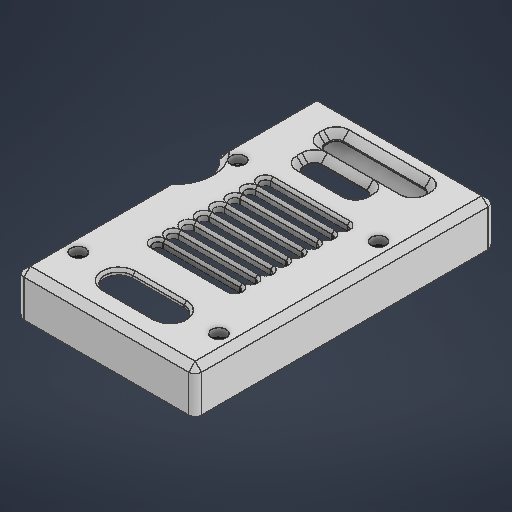
# Autodesk Inventor part: m3 case
Saved by Autodesk Inventor 2027.1 (Build 311270010, 270A)
## iProperties
Created: 2026-10-13
Part Number: m3 case
Material: 일반
Document SubType Name: Modeling
Designer: work
Density: 1 g/cm^3
Appearance: 기본값
Author: work
Autodesk Inventor part; units mm, degrees
ref_plane "YZ Plane" through (0, 0, 0) normal (1, 0, 0) x (0, 1, 0)
ref_plane "XZ Plane" through (0, 0, 0) normal (0, 1, 0) x (-1, 0, 0)
ref_plane "XY Plane" through (0, 0, 0) normal (0, 0, 1) x (1, 0, 0)
sketch "스케치1" plane through (0, 0, 0) normal (0, 1, 0) x (-1, 0, 0)
  line L0 (0, 0) -> (69.41, 0)
  line L1 (69.41, 0) -> (69.41, -117.01)
  line L2 (69.41, -117.01) -> (0, -117.01)
  line L3 (0, -117.01) -> (0, 0)
  line L4 (62.205, -16.5) -> (7.205, -16.5) construction
  line L5 (7.205, -16.5) -> (7.205, -78.9) construction
  line L6 (7.205, -78.9) -> (62.205, -78.9) construction
  line L7 (62.205, -78.9) -> (62.205, -16.5) construction
  line L8 (66.91, -114.51) -> (66.91, -2.5)
  line L9 (66.91, -2.5) -> (2.5, -2.5)
  line L10 (2.5, -2.5) -> (2.5, -114.51)
  line L11 (2.5, -114.51) -> (66.91, -114.51)
  circle A0 centre (7.205, -16.5) radius 1.55
  circle A1 centre (62.205, -16.5) radius 1.55
  circle A2 centre (62.205, -78.9) radius 1.55
  circle A3 centre (7.205, -78.9) radius 1.55
  circle A4 centre (7.205, -16.5) radius 2.5
  circle A5 centre (7.205, -78.9) radius 2.5
  circle A6 centre (62.205, -78.9) radius 2.5
  circle A7 centre (62.205, -16.5) radius 2.5
  line L12 (49.705, -89.4) -> (26.705, -89.4)
  line L13 (26.705, -89.4) -> (26.705, -96.4)
  line L14 (26.705, -96.4) -> (49.705, -96.4)
  line L15 (49.705, -96.4) -> (49.705, -89.4)
  line L16 (53.205, -101.4) -> (16.205, -101.4)
  line L17 (16.205, -101.4) -> (16.205, -108.4)
  line L18 (16.205, -108.4) -> (53.205, -108.4)
  line L19 (53.205, -108.4) -> (53.205, -101.4)
  line L20 (69.41, -68.9) -> (64.41, -68.9) construction
  arc A8 (69.41, -58.9) -> (69.41, -78.9) centre (76.91, -68.9) ccw
  point P0 (34.705, 0)
  point P1 (34.705, -16.5)
  point P2 (38.205, -89.4)
  point P3 (49.705, -92.9)
  point P4 (34.705, -108.4)
  point P5 (34.705, -114.51)
  point P6 (66.91, -68.9)
  point P7 (66.91, -76.4)
  point P8 (66.91, -61.4)
  dimension "d0" = 69.41
  dimension "d1" = 117.01
  dimension "d2" = 55
  dimension "d3" = 62.4
  dimension "d4" = 16.5
  dimension "d5" = 2.5
  dimension "d6" = 3.1
  dimension "d7" = 3.1
  dimension "d8" = 3.1
  dimension "d9" = 3.1
  dimension "d10" = 5
  dimension "d11" = 5
  dimension "d12" = 5
  dimension "d13" = 5
  dimension "d14" = 24
  dimension "d15" = 14
  dimension "d16" = 7
  dimension "d17" = 23
  dimension "d18" = 5
  dimension "d19" = 37
  dimension "d20" = 7
  dimension "d21" = 5
  dimension "d22" = 10
  dimension "d23" = 20
  constraints: 42 end point, 10 parallel, 9 centre point, 8 coincident, 7 midpoint, 5 horizontal, 5 perpendicular, 3 point on circle, 3 point on line, 2 vertical alignment, 1 line through centre, 3 other
  measures "d0" distance of L1.end L2.end
  measures "d1" distance of L0.end L1.end
  measures "d2" distance of L6.end L5.end
  measures "d3" distance of L6.end L4.start
  measures "d4" distance from line of point (34.705, 0) L4
  measures "d5" distance between parallel lines of L1 L8
  measures "d6" diameter of A0
  measures "d7" diameter of A3
  measures "d8" diameter of A1
  measures "d9" diameter of A2
  measures "d10" diameter of A4
  measures "d11" diameter of A5
  measures "d12" diameter of A6
  measures "d13" diameter of A7
  measures "d14" horizontal distance of L6.end point (38.205, -89.4)
  measures "d15" vertical distance of L6.end point (49.705, -92.9)
  measures "d16" distance of L14.end L12.start
  measures "d17" distance of L12.start L12.end
  measures "d18" distance between parallel lines of L14 L16
  measures "d19" distance of L16.start L16.end
  measures "d20" distance of L16.end L17.end
  measures "d21" distance of L20.start L20.end
  measures "d22" vertical distance of point (66.91, -68.9) L6.end
  measures "d23" distance of A8.end A8.start
extrude "돌출1" add sketch "스케치1" along normal blind 3 contours L0 L1 A8 L8 L9 L10 L11 L2 L3 | A8 L8 L11 L10 L9 | A4 | A5 | A6 | A7
extrude "돌출2" add sketch "스케치1" against normal blind 14 contours L0 L1 A8 L8 L9 L10 L11 L2 L3
extrude "돌출3" add sketch "스케치1" against normal blind 8 contours A4 | A5 | A6 | A7
fillet "모깎기1" radius 2.5 18 edges at (-69.41, -5.5, -117.01) (0, -5.5, 0) (-69.41, -5.5, 0) (-69.41, -5.5, -58.9) (-49.705, 1.5, -96.4) (-49.705, 1.5, -89.4) (0, -5.5, -117.01) (-53.205, 1.5, -101.4) (-53.205, 1.5, -108.4) (-16.205, 1.5, -108.4) (-16.205, 1.5, -101.4) (-69.41, -5.5, -78.9) (-26.705, 1.5, -96.4) (-26.705, 1.5, -89.4) (-66.91, -7, -2.5) (-66.91, -7, -114.51) (-2.5, -7, -114.51) (-2.5, -7, -2.5)
chamfer "모따기1" distance 2.5 angle 45 28 edges at (-48.9728, 3, -95.6678) (-49.705, 3, -92.9) (-48.9728, 3, -90.1322) (-38.205, 3, -89.4) (-27.4372, 3, -90.1322) (-26.705, 3, -92.9) (-27.4372, 3, -95.6678) (-38.205, 3, -96.4) (-52.4728, 3, -102.1322) (-34.705, 3, -101.4) (-16.9372, 3, -102.1322) (-16.205, 3, -104.9) (-16.9372, 3, -107.6678) (-34.705, 3, -108.4) (-52.4728, 3, -107.6678) (-53.205, 3, -104.9) (-64.41, 3, -68.9) (-69.1922, 3, -58.7403) (-69.41, 3, -30.1098) (-68.6778, 3, -0.7322) (-34.705, 3, 0) (-0.7322, 3, -0.7322) (0, 3, -58.505) (-0.7322, 3, -116.2778) (-34.705, 3, -117.01) (-68.6778, 3, -116.2778) (-69.41, 3, -97.2952) (-69.1922, 3, -79.0597)
sketch "스케치2" plane through (0, 0, 0) normal (0, -1, 0) x (1, 0, 0)
  line L0 (-19.705, -35.2) -> (-49.705, -35.2) construction
  line L1 (-19.705, -33.2) -> (-49.705, -33.2)
  line L2 (-49.705, -37.2) -> (-19.705, -37.2)
  arc A0 (-19.705, -37.2) -> (-19.705, -33.2) centre (-19.705, -35.2) ccw
  arc A1 (-49.705, -33.2) -> (-49.705, -37.2) centre (-49.705, -35.2) ccw
  line L3 (-64.41, -2.5) -> (-5, -2.5) projected
  line L4 (-19.205, -4.5) -> (-50.205, -4.5)
  line L5 (-50.205, -4.5) -> (-50.205, -25.2)
  line L6 (-50.205, -25.2) -> (-19.205, -25.2)
  line L7 (-19.205, -25.2) -> (-19.205, -4.5)
  arc A2 (-49.705, -39.2) -> (-49.705, -43.2) centre (-49.705, -41.2) ccw
  line L8 (-49.705, -43.2) -> (-19.705, -43.2)
  arc A3 (-19.705, -43.2) -> (-19.705, -39.2) centre (-19.705, -41.2) ccw
  line L9 (-19.705, -41.2) -> (-49.705, -41.2) construction
  line L10 (-19.705, -39.2) -> (-49.705, -39.2)
  arc A4 (-49.705, -45.2) -> (-49.705, -49.2) centre (-49.705, -47.2) ccw
  line L11 (-49.705, -49.2) -> (-19.705, -49.2)
  arc A5 (-19.705, -49.2) -> (-19.705, -45.2) centre (-19.705, -47.2) ccw
  line L12 (-19.705, -47.2) -> (-49.705, -47.2) construction
  line L13 (-19.705, -45.2) -> (-49.705, -45.2)
  arc A6 (-49.705, -51.2) -> (-49.705, -55.2) centre (-49.705, -53.2) ccw
  line L14 (-49.705, -55.2) -> (-19.705, -55.2)
  arc A7 (-19.705, -55.2) -> (-19.705, -51.2) centre (-19.705, -53.2) ccw
  line L15 (-19.705, -53.2) -> (-49.705, -53.2) construction
  line L16 (-19.705, -51.2) -> (-49.705, -51.2)
  arc A8 (-49.705, -57.2) -> (-49.705, -61.2) centre (-49.705, -59.2) ccw
  line L17 (-49.705, -61.2) -> (-19.705, -61.2)
  arc A9 (-19.705, -61.2) -> (-19.705, -57.2) centre (-19.705, -59.2) ccw
  line L18 (-19.705, -59.2) -> (-49.705, -59.2) construction
  line L19 (-19.705, -57.2) -> (-49.705, -57.2)
  arc A10 (-49.705, -63.2) -> (-49.705, -67.2) centre (-49.705, -65.2) ccw
  line L20 (-49.705, -67.2) -> (-19.705, -67.2)
  arc A11 (-19.705, -67.2) -> (-19.705, -63.2) centre (-19.705, -65.2) ccw
  line L21 (-19.705, -65.2) -> (-49.705, -65.2) construction
  line L22 (-19.705, -63.2) -> (-49.705, -63.2)
  arc A12 (-49.705, -69.2) -> (-49.705, -73.2) centre (-49.705, -71.2) ccw
  line L23 (-49.705, -73.2) -> (-19.705, -73.2)
  arc A13 (-19.705, -73.2) -> (-19.705, -69.2) centre (-19.705, -71.2) ccw
  line L24 (-19.705, -71.2) -> (-49.705, -71.2) construction
  line L25 (-19.705, -69.2) -> (-49.705, -69.2)
  arc A14 (-49.705, -75.2) -> (-49.705, -79.2) centre (-49.705, -77.2) ccw
  line L26 (-49.705, -79.2) -> (-19.705, -79.2)
  arc A15 (-19.705, -79.2) -> (-19.705, -75.2) centre (-19.705, -77.2) ccw
  line L27 (-19.705, -77.2) -> (-49.705, -77.2) construction
  line L28 (-19.705, -75.2) -> (-49.705, -75.2)
  line L29 (-44.705, -14.85) -> (-24.705, -14.85) construction
  line L30 (-44.705, -20.35) -> (-24.705, -20.35)
  line L31 (-24.705, -9.35) -> (-44.705, -9.35)
  arc A16 (-44.705, -9.35) -> (-44.705, -20.35) centre (-44.705, -14.85) ccw
  arc A17 (-24.705, -20.35) -> (-24.705, -9.35) centre (-24.705, -14.85) ccw
  line L32 (-50.205, -14.85) -> (-55.205, -14.85) construction
  line L33 (-50.205, -13.35) -> (-55.205, -13.35)
  line L34 (-55.205, -16.35) -> (-50.205, -16.35)
  arc A18 (-50.205, -16.35) -> (-50.205, -13.35) centre (-50.205, -14.85) ccw
  arc A19 (-55.205, -13.35) -> (-55.205, -16.35) centre (-55.205, -14.85) ccw
  point P0 (0, 0)
  point P1 (-34.705, -35.2)
  point P2 (-34.705, -2.5)
  point P3 (-34.705, -4.5)
  point P4 (-34.705, -2.5)
  point P5 (-34.705, -25.2)
  point P6 (-34.705, -41.2)
  point P7 (-34.705, -47.2)
  point P8 (-34.705, -53.2)
  point P9 (-34.705, -59.2)
  point P10 (-34.705, -65.2)
  point P11 (-34.705, -71.2)
  point P12 (-34.705, -77.2)
  point P13 (-34.705, -14.85)
  point P14 (-19.205, -14.85)
  point P15 (-52.705, -14.85)
  point P16 (-50.0005, -13.364)
  point P17 (-50.0005, -16.336)
  point P18 (-19.205, -14.85)
  dimension "d34" = 20.7
  dimension "d35" = 31
  dimension "d36" = 2
  dimension "d37" = 10
  dimension "d38" = 30
  dimension "d39" = 4
  dimension "d42" = 6
  dimension "d47" = 10
  dimension "d48" = 5
  dimension "d49" = 3
  constraints: 88 end point, 41 point on circle, 20 centre point, 13 tangent, 8 midpoint, 5 parallel, 4 horizontal, 3 vertical alignment, 1 horizontal alignment, 1 perpendicular, 1 vertical, 84 other
  measures "d34" distance of L4.end L5.end
  measures "d35" distance of L4.start L4.end
  measures "d36" distance between parallel lines of L3 L4
  measures "d37" distance of point (-34.705, -25.2) point (-34.705, -35.2)
  measures "d38" distance of L0.start L0.end
  measures "d39" distance between parallel lines of L1 L2
  measures "d42" distance of L0.end L9.end
  measures "d47" distance of point (-34.705, -14.85) L29.end
  measures "d48" distance of L32.start L32.end
  measures "d49" diameter of A19
extrude "돌출4" cut sketch "스케치2" against normal through all contours A0 L2 A1 L1 | A17 L30 A16 A18 L31 | A16 A18 | L10 A3 L8 A2 | L13 A5 L11 A4 | L16 A7 L14 A6 | L19 A9 L17 A8 | L22 A11 L20 A10 | L25 A13 L23 A12 | L28 A15 L26 A14
extrude "돌출5" cut sketch "스케치2" against normal blind 1 contours L7 A17 L31 A16 A18 L5 L4 | L7 L6 L5 A18 A16 L30 A17 | A18 A16 L5 | L5 L34 A19 L33 | A16 A18 L5
fillet "모깎기2" radius 2.5 2 edges at (-50.205, 0.5, -13.35) (-50.205, 0.5, -16.35)
fillet "모깎기3" radius 4 4 edges at (-19.205, 0.5, -4.5) (-19.205, 0.5, -25.2) (-50.205, 0.5, -25.2) (-50.205, 0.5, -4.5)
chamfer "모따기2" distance 1 angle 45 36 edges at (-34.705, 3, -20.35) (-19.205, 3, -14.85) (-34.705, 3, -9.35) (-50.205, 3, -14.85) (-34.705, 3, -33.2) (-51.705, 3, -35.2) (-34.705, 3, -37.2) (-17.705, 3, -35.2) (-51.705, 3, -41.2) (-34.705, 3, -43.2) (-17.705, 3, -41.2) (-34.705, 3, -39.2) (-51.705, 3, -47.2) (-34.705, 3, -49.2) (-17.705, 3, -47.2) (-34.705, 3, -45.2) (-51.705, 3, -53.2) (-34.705, 3, -55.2) (-17.705, 3, -53.2) (-34.705, 3, -51.2) (-51.705, 3, -59.2) (-34.705, 3, -61.2) (-17.705, 3, -59.2) (-34.705, 3, -57.2) (-51.705, 3, -65.2) (-34.705, 3, -67.2) (-17.705, 3, -65.2) (-34.705, 3, -63.2) (-51.705, 3, -71.2) (-34.705, 3, -73.2) (-17.705, 3, -71.2) (-34.705, 3, -69.2) (-51.705, 3, -77.2) (-34.705, 3, -79.2) (-17.705, 3, -77.2) (-34.705, 3, -75.2)
sketch "스케치3" plane through (0, 0, 0) normal (0, -1, 0) x (1, 0, 0)
  line L0 (-65.41, -57.5) -> (-52.91, -57.5)
  line L1 (-52.91, -57.5) -> (-52.91, -21.5)
  line L2 (-52.91, -21.5) -> (-65.41, -21.5)
  line L3 (-65.41, -21.5) -> (-65.41, -57.5)
  line L4 (-66.91, -61.4) -> (-66.91, -5) projected
  circle A0 centre (-62.205, -16.5) radius 1.55 projected
  point P0 (0, 0)
  dimension "d59" = 36
  dimension "d60" = 12.5
  dimension "d61" = 1.5
  dimension "d64" = 5
  constraints: 8 end point, 2 parallel, 1 horizontal, 1 perpendicular
  measures "d59" distance of L0.end L1.end
  measures "d60" distance of L1.end L2.end
  measures "d61" distance between parallel lines of L4 L3
  measures "d64" distance from line of A0.centre L2
extrude "돌출6" cut sketch "스케치3" against normal blind 2 contours L3 L2 L1 L0
sketch "스케치4" plane through (0, 0, 0) normal (0, -1, 0) x (1, 0, 0)
  line L0 (-65.41, -57.5) -> (-65.41, -21.5) projected
  line L1 (-65.41, -21.5) -> (-52.91, -21.5) projected
  line L2 (-52.91, -21.5) -> (-52.91, -57.5) projected
  line L3 (-52.91, -57.5) -> (-65.41, -57.5) projected
  arc A0 (-50.705, -101.4) -> (-53.205, -103.9) centre (-50.705, -103.9) ccw projected
  line L4 (-18.705, -101.4) -> (-50.705, -101.4) projected
  arc A1 (-16.205, -103.9) -> (-18.705, -101.4) centre (-18.705, -103.9) ccw projected
  line L5 (-16.205, -105.9) -> (-16.205, -103.9) projected
  arc A2 (-18.705, -108.4) -> (-16.205, -105.9) centre (-18.705, -105.9) ccw projected
  line L6 (-50.705, -108.4) -> (-18.705, -108.4) projected
  arc A3 (-53.205, -105.9) -> (-50.705, -108.4) centre (-50.705, -105.9) ccw projected
  line L7 (-53.205, -103.9) -> (-53.205, -105.9) projected
  arc A4 (-47.205, -89.4) -> (-49.705, -91.9) centre (-47.205, -91.9) ccw projected
  line L8 (-29.205, -89.4) -> (-47.205, -89.4) projected
  arc A5 (-26.705, -91.9) -> (-29.205, -89.4) centre (-29.205, -91.9) ccw projected
  line L9 (-26.705, -93.9) -> (-26.705, -91.9) projected
  arc A6 (-29.205, -96.4) -> (-26.705, -93.9) centre (-29.205, -93.9) ccw projected
  line L10 (-47.205, -96.4) -> (-29.205, -96.4) projected
  arc A7 (-49.705, -93.9) -> (-47.205, -96.4) centre (-47.205, -93.9) ccw projected
  line L11 (-49.705, -91.9) -> (-49.705, -93.9) projected
  circle A8 centre (-7.205, -78.9) radius 2.5 projected
  circle A9 centre (-7.205, -16.5) radius 2.5 projected
  circle A10 centre (-62.205, -78.9) radius 2.5 projected
  circle A11 centre (-62.205, -16.5) radius 2.5 projected
  arc A12 (-2.5, -5) -> (-5, -2.5) centre (-5, -5) ccw projected
  line L12 (-5, -2.5) -> (-64.41, -2.5) projected
  arc A13 (-64.41, -2.5) -> (-66.91, -5) centre (-64.41, -5) ccw projected
  line L13 (-66.91, -5) -> (-66.91, -61.4) projected
  arc A14 (-66.91, -76.4) -> (-66.91, -61.4) centre (-76.91, -68.9) ccw projected
  line L14 (-66.91, -76.4) -> (-66.91, -112.01) projected
  arc A15 (-66.91, -112.01) -> (-64.41, -114.51) centre (-64.41, -112.01) ccw projected
  line L15 (-64.41, -114.51) -> (-5, -114.51) projected
  arc A16 (-5, -114.51) -> (-2.5, -112.01) centre (-5, -112.01) ccw projected
  line L16 (-2.5, -112.01) -> (-2.5, -5) projected
  arc A17 (-19.705, -43.2) -> (-19.705, -39.2) centre (-19.705, -41.2) ccw projected
  line L17 (-19.705, -43.2) -> (-49.705, -43.2) projected
  arc A18 (-49.705, -39.2) -> (-49.705, -43.2) centre (-49.705, -41.2) ccw projected
  line L18 (-49.705, -39.2) -> (-19.705, -39.2) projected
  arc A19 (-19.705, -61.2) -> (-19.705, -57.2) centre (-19.705, -59.2) ccw projected
  line L19 (-19.705, -61.2) -> (-49.705, -61.2) projected
  arc A20 (-49.705, -57.2) -> (-49.705, -61.2) centre (-49.705, -59.2) ccw projected
  line L20 (-49.705, -57.2) -> (-19.705, -57.2) projected
  arc A21 (-19.705, -79.2) -> (-19.705, -75.2) centre (-19.705, -77.2) ccw projected
  line L21 (-19.705, -79.2) -> (-49.705, -79.2) projected
  arc A22 (-49.705, -75.2) -> (-49.705, -79.2) centre (-49.705, -77.2) ccw projected
  line L22 (-49.705, -75.2) -> (-19.705, -75.2) projected
  arc A23 (-19.705, -55.2) -> (-19.705, -51.2) centre (-19.705, -53.2) ccw projected
  line L23 (-19.705, -55.2) -> (-49.705, -55.2) projected
  arc A24 (-49.705, -51.2) -> (-49.705, -55.2) centre (-49.705, -53.2) ccw projected
  line L24 (-49.705, -51.2) -> (-19.705, -51.2) projected
  line L25 (-19.705, -37.2) -> (-49.705, -37.2) projected
  arc A25 (-49.705, -33.2) -> (-49.705, -37.2) centre (-49.705, -35.2) ccw projected
  line L26 (-49.705, -33.2) -> (-19.705, -33.2) projected
  arc A26 (-19.705, -37.2) -> (-19.705, -33.2) centre (-19.705, -35.2) ccw projected
  arc A27 (-19.705, -67.2) -> (-19.705, -63.2) centre (-19.705, -65.2) ccw projected
  line L27 (-19.705, -67.2) -> (-49.705, -67.2) projected
  arc A28 (-49.705, -63.2) -> (-49.705, -67.2) centre (-49.705, -65.2) ccw projected
  line L28 (-49.705, -63.2) -> (-19.705, -63.2) projected
  arc A29 (-19.705, -73.2) -> (-19.705, -69.2) centre (-19.705, -71.2) ccw projected
  line L29 (-19.705, -73.2) -> (-49.705, -73.2) projected
  arc A30 (-49.705, -69.2) -> (-49.705, -73.2) centre (-49.705, -71.2) ccw projected
  line L30 (-49.705, -69.2) -> (-19.705, -69.2) projected
  arc A31 (-19.705, -49.2) -> (-19.705, -45.2) centre (-19.705, -47.2) ccw projected
  line L31 (-19.705, -49.2) -> (-49.705, -49.2) projected
  arc A32 (-49.705, -45.2) -> (-49.705, -49.2) centre (-49.705, -47.2) ccw projected
  line L32 (-49.705, -45.2) -> (-19.705, -45.2) projected
  arc A33 (-50.205, -18.85) -> (-52.705, -16.35) centre (-52.705, -18.85) ccw projected
  line L33 (-52.705, -16.35) -> (-55.205, -16.35) projected
  arc A34 (-55.205, -13.35) -> (-55.205, -16.35) centre (-55.205, -14.85) ccw projected
  line L34 (-55.205, -13.35) -> (-52.705, -13.35) projected
  arc A35 (-52.705, -13.35) -> (-50.205, -10.85) centre (-52.705, -10.85) ccw projected
  line L35 (-50.205, -10.85) -> (-50.205, -8.5) projected
  arc A36 (-46.205, -4.5) -> (-50.205, -8.5) centre (-46.205, -8.5) ccw projected
  line L36 (-46.205, -4.5) -> (-23.205, -4.5) projected
  arc A37 (-19.205, -8.5) -> (-23.205, -4.5) centre (-23.205, -8.5) ccw projected
  line L37 (-19.205, -8.5) -> (-19.205, -21.2) projected
  arc A38 (-23.205, -25.2) -> (-19.205, -21.2) centre (-23.205, -21.2) ccw projected
  line L38 (-23.205, -25.2) -> (-46.205, -25.2) projected
  arc A39 (-50.205, -21.2) -> (-46.205, -25.2) centre (-46.205, -21.2) ccw projected
  line L39 (-50.205, -21.2) -> (-50.205, -18.85) projected
  circle A40 centre (-7.205, -78.9) radius 1.55 projected
  line L40 (-7.205, -78.9) -> (-2.5, -78.9) construction
  line L41 (-7.205, -83.9) -> (-2.5, -83.9)
  line L42 (-2.5, -73.9) -> (-7.205, -73.9)
  arc A41 (-7.205, -73.9) -> (-7.205, -83.9) centre (-7.205, -78.9) ccw
  arc A42 (-2.5, -83.9) -> (-2.5, -73.9) centre (-2.5, -78.9) ccw
  line L43 (-62.205, -78.9) -> (-66.91, -78.9) construction
  line L44 (-62.205, -76.4) -> (-66.91, -76.4)
  line L45 (-66.91, -81.4) -> (-62.205, -81.4)
  arc A43 (-62.205, -81.4) -> (-62.205, -76.4) centre (-62.205, -78.9) ccw
  arc A44 (-66.91, -76.4) -> (-66.91, -81.4) centre (-66.91, -78.9) ccw
  circle A45 centre (-62.205, -16.5) radius 1.55 projected
  line L46 (-62.205, -16.5) -> (-66.91, -16.5) construction
  line L47 (-62.205, -11.5) -> (-66.91, -11.5)
  line L48 (-66.91, -21.5) -> (-62.205, -21.5)
  arc A46 (-62.205, -21.5) -> (-62.205, -11.5) centre (-62.205, -16.5) ccw
  arc A47 (-66.91, -11.5) -> (-66.91, -21.5) centre (-66.91, -16.5) ccw
  circle A48 centre (-7.205, -16.5) radius 1.55 projected
  line L49 (-7.205, -16.5) -> (-2.5, -16.5) construction
  line L50 (-7.205, -21.5) -> (-2.5, -21.5)
  line L51 (-2.5, -11.5) -> (-7.205, -11.5)
  arc A49 (-7.205, -11.5) -> (-7.205, -21.5) centre (-7.205, -16.5) ccw
  arc A50 (-2.5, -21.5) -> (-2.5, -11.5) centre (-2.5, -16.5) ccw
  point P0 (0, 0)
  point P1 (-4.8525, -78.9)
  point P2 (-64.5575, -78.9)
  point P3 (-64.5575, -16.5)
  point P4 (-4.8525, -16.5)
  dimension "d65" = 10
  dimension "d67" = 10
  dimension "d68" = 10
  constraints: 32 end point, 16 point on circle, 16 tangent, 8 centre point, 6 point on line, 4 midpoint, 4 parallel, 3 perpendicular
  measures "d65" diameter of A42
  measures "d67" diameter of A47
  measures "d68" diameter of A50
extrude "돌출7" add sketch "스케치4" along normal up to surface (8 mm away) contours L48 L13 L47 A46 L1 | L44 A10 L45 L14 | L16 L50 A49 L51 | L16 L41 A41 L42
fillet "모깎기4" radius 3 6 edges at (-66.91, -4, -11.5) (-66.91, -4, -81.4) (-2.5, -4, -21.5) (-2.5, -4, -11.5) (-2.5, -4, -73.9) (-2.5, -4, -83.9)
chamfer "모따기3" distance 1 angle 45 28 edges at (-2.5, 0, -47.7) (-3.3787, 0, -22.3787) (-6.3525, 0, -21.5) (-12.205, 0, -16.5) (-6.3525, 0, -11.5) (-3.3787, 0, -10.6213) (-2.5, 0, -6.75) (-3.2322, 0, -3.2322) (-34.705, 0, -2.5) (-66.1778, 0, -3.2322) (-66.91, 0, -6.75) (-66.0313, 0, -10.6213) (-63.0575, 0, -11.5) (-57.205, 0, -16.5) (-3.3787, 0, -73.0213) (-6.3525, 0, -73.9) (-12.205, 0, -78.9) (-6.3525, 0, -83.9) (-3.3787, 0, -84.7787) (-2.5, 0, -99.455) (-3.2322, 0, -113.7778) (-34.705, 0, -114.51) (-66.1778, 0, -113.7778) (-66.91, 0, -98.205) (-66.0313, 0, -82.2787) (-63.0575, 0, -81.4) (-59.705, 0, -78.9) (-64.5575, 0, -76.4)
sketch "스케치5" plane through (0, 3, 0) normal (0, 1, 0) x (1, 0, 0)
  arc A0 (-19.705, 74.2) -> (-19.705, 80.2) centre (-19.705, 77.2) ccw projected
  arc A1 (-19.705, 68.2) -> (-19.705, 74.2) centre (-19.705, 71.2) ccw projected
  arc A2 (-19.705, 62.2) -> (-19.705, 68.2) centre (-19.705, 65.2) ccw projected
  arc A3 (-19.705, 56.2) -> (-19.705, 62.2) centre (-19.705, 59.2) ccw projected
  arc A4 (-19.705, 50.2) -> (-19.705, 56.2) centre (-19.705, 53.2) ccw projected
  arc A5 (-19.705, 44.2) -> (-19.705, 50.2) centre (-19.705, 47.2) ccw projected
  arc A6 (-19.705, 38.2) -> (-19.705, 44.2) centre (-19.705, 41.2) ccw projected
  arc A7 (-19.705, 32.2) -> (-19.705, 38.2) centre (-19.705, 35.2) ccw projected
  line L0 (-49.705, 32.2) -> (-19.705, 32.2) projected
  arc A8 (-49.705, 38.2) -> (-49.705, 32.2) centre (-49.705, 35.2) ccw projected
  arc A9 (-49.705, 44.2) -> (-49.705, 38.2) centre (-49.705, 41.2) ccw projected
  arc A10 (-49.705, 50.2) -> (-49.705, 44.2) centre (-49.705, 47.2) ccw projected
  arc A11 (-49.705, 56.2) -> (-49.705, 50.2) centre (-49.705, 53.2) ccw projected
  arc A12 (-49.705, 62.2) -> (-49.705, 56.2) centre (-49.705, 59.2) ccw projected
  arc A13 (-49.705, 68.2) -> (-49.705, 62.2) centre (-49.705, 65.2) ccw projected
  arc A14 (-49.705, 74.2) -> (-49.705, 68.2) centre (-49.705, 71.2) ccw projected
  arc A15 (-49.705, 80.2) -> (-49.705, 74.2) centre (-49.705, 77.2) ccw projected
  line L1 (-19.705, 80.2) -> (-49.705, 80.2) projected
  line L2 (-24.705, 21.35) -> (-44.705, 21.35) projected
  arc A16 (-24.705, 8.35) -> (-24.705, 21.35) centre (-24.705, 14.85) ccw projected
  line L3 (-44.705, 8.35) -> (-24.705, 8.35) projected
  arc A17 (-44.705, 21.35) -> (-44.705, 8.35) centre (-44.705, 14.85) ccw projected
  circle A18 centre (-62.205, 16.5) radius 1.55 projected
  circle A19 centre (-62.205, 78.9) radius 1.55 projected
  circle A20 centre (-7.205, 78.9) radius 1.55 projected
  circle A21 centre (-7.205, 16.5) radius 1.55 projected
  line L4 (-29.205, 98.9) -> (-18.705, 98.9) projected
  arc A22 (-24.205, 93.9) -> (-29.205, 98.9) centre (-29.205, 93.9) ccw projected
  line L5 (-24.205, 91.9) -> (-24.205, 93.9) projected
  arc A23 (-29.205, 86.9) -> (-24.205, 91.9) centre (-29.205, 91.9) ccw projected
  line L6 (-47.205, 86.9) -> (-29.205, 86.9) projected
  arc A24 (-52.205, 91.9) -> (-47.205, 86.9) centre (-47.205, 91.9) ccw projected
  line L7 (-52.205, 93.9) -> (-52.205, 91.9) projected
  arc A25 (-47.205, 98.9) -> (-52.205, 93.9) centre (-47.205, 93.9) ccw projected
  line L8 (-50.705, 98.9) -> (-47.205, 98.9) projected
  arc A26 (-55.705, 103.9) -> (-50.705, 98.9) centre (-50.705, 103.9) ccw projected
  line L9 (-55.705, 105.9) -> (-55.705, 103.9) projected
  arc A27 (-50.705, 110.9) -> (-55.705, 105.9) centre (-50.705, 105.9) ccw projected
  line L10 (-18.705, 110.9) -> (-50.705, 110.9) projected
  arc A28 (-13.705, 105.9) -> (-18.705, 110.9) centre (-18.705, 105.9) ccw projected
  line L11 (-13.705, 103.9) -> (-13.705, 105.9) projected
  arc A29 (-18.705, 98.9) -> (-13.705, 103.9) centre (-18.705, 103.9) ccw projected
  line L12 (-66.91, 80.0803) -> (-66.91, 114.51) projected
  arc A30 (-66.91, 57.7197) -> (-66.91, 80.0803) centre (-76.91, 68.9) ccw projected
  line L13 (-66.91, 2.5) -> (-66.91, 57.7197) projected
  line L14 (-2.5, 2.5) -> (-66.91, 2.5) projected
  line L15 (-2.5, 114.51) -> (-2.5, 2.5) projected
  line L16 (-66.91, 114.51) -> (-2.5, 114.51) projected
  arc A31 (-7.205, 83.9) -> (-7.205, 73.9) centre (-7.205, 78.9) ccw projected
  point P0 (0, 0)
  constraints: 4 coincident
hole "구멍1" at (-7.205, 3, -16.5) at (-62.205, 3, -16.5) at (-62.205, 3, -78.9) at (-7.205, 3, -78.9) direction (0, -1, 0) diameter 4 end through all counterbore diameter 5.7 counterbore depth 3.2
equation "\"d7\" = d6"
equation "\"d8\" = d6"
equation "\"d9\" = d6"
